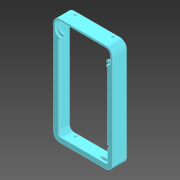
# Autodesk Inventor part: outer shell
Saved by Autodesk Inventor 2020.1 (Build 241239000, 239)
## iProperties
Created: 2026-10-11
Part Number: outer shell
Material: Generic
Document SubType Name: Modeling
Designer: willn
Density: 1 g/cm^3
Appearance: Default
Author: willn
Autodesk Inventor part; units mm, degrees
ref_plane "YZ Plane" through (0, 0, 0) normal (1, 0, 0) x (0, 1, 0)
ref_plane "XZ Plane" through (0, 0, 0) normal (0, 1, 0) x (-1, 0, 0)
ref_plane "XY Plane" through (0, 0, 0) normal (0, 0, 1) x (1, 0, 0)
sketch "Sketch2" plane through (0, 0, 0) normal (0, 0, 1) x (1, 0, 0)
  arc A0 (60, 95.25) -> (56, 99.25) centre (56, 95.25) ccw construction
  line L0 (4, 99.25) -> (56, 99.25) construction
  arc A1 (4, 99.25) -> (0, 95.25) centre (4, 95.25) ccw construction
  line L1 (0, 4) -> (0, 95.25) construction
  arc A2 (0, 4) -> (4, 0) centre (4, 4) ccw construction
  line L2 (56, 0) -> (4, 0) construction
  arc A3 (56, 0) -> (60, 4) centre (56, 4) ccw construction
  line L3 (60, 95.25) -> (60, 4) construction
  circle A4 centre (6.25, 4.05) radius 0.5 construction
  circle A5 centre (14.25, 4.05) radius 0.5 construction
  circle A6 centre (22.2572, 12.9646) radius 0.55 construction
  circle A7 centre (30.0354, 20.7428) radius 0.55 construction
  circle A8 centre (5.5, 27.45) radius 0.5 construction
  circle A9 centre (42.5, 8.25) radius 0.4 construction
  circle A10 centre (42.5, 10.25) radius 0.4 construction
  circle A11 centre (47.88, 23.87) radius 0.375 construction
  circle A12 centre (47.88, 25.87) radius 0.375 construction
  circle A13 centre (54.5, 27.45) radius 0.5 construction
  circle A14 centre (58.15, 29.93) radius 0.5 construction
  circle A15 centre (58.15, 32.47) radius 0.5 construction
  circle A16 centre (58.15, 35.01) radius 0.5 construction
  circle A17 centre (58.15, 37.55) radius 0.5 construction
  circle A18 centre (10.25, 88.95) radius 0.4 construction
  circle A19 centre (5.5, 95.75) radius 0.5 construction
  circle A20 centre (10.25, 90.95) radius 0.4 construction
  arc A21 (19.25, 75.25) -> (18.25, 74.25) centre (19.25, 74.25) ccw construction
  line L4 (40.75, 75.25) -> (19.25, 75.25) construction
  arc A22 (41.75, 74.25) -> (40.75, 75.25) centre (40.75, 74.25) ccw construction
  arc A23 (40.75, 73.25) -> (41.75, 74.25) centre (40.75, 74.25) ccw construction
  line L5 (19.25, 73.25) -> (40.75, 73.25) construction
  arc A24 (18.25, 74.25) -> (19.25, 73.25) centre (19.25, 74.25) ccw construction
  arc A25 (55.85, 77.95) -> (54.85, 76.95) centre (55.85, 76.95) ccw construction
  line L6 (56.85, 77.95) -> (55.85, 77.95) construction
  arc A26 (57.85, 76.95) -> (56.85, 77.95) centre (56.85, 76.95) ccw construction
  line L7 (57.85, 74.95) -> (57.85, 76.95) construction
  arc A27 (56.85, 73.95) -> (57.85, 74.95) centre (56.85, 74.95) ccw construction
  line L8 (55.85, 73.95) -> (56.85, 73.95) construction
  arc A28 (54.85, 74.95) -> (55.85, 73.95) centre (55.85, 74.95) ccw construction
  line L9 (54.85, 76.95) -> (54.85, 74.95) construction
  circle A29 centre (57.15, 84.82) radius 0.5 construction
  circle A30 centre (57.15, 87.36) radius 0.5 construction
  circle A31 centre (57.15, 89.9) radius 0.5 construction
  circle A32 centre (54.5, 95.75) radius 0.5 construction
  circle A33 centre (57.15, 92.44) radius 0.5 construction
  circle A34 centre (57.15, 94.98) radius 0.5 construction
  line L10 (54.05, 116.3) -> (6.05, 116.3) construction
  line L11 (6.05, 116.3) -> (6.05, 96.3) construction
  line L12 (6.05, 96.3) -> (54.05, 96.3) construction
  line L13 (54.05, 96.3) -> (54.05, 116.3) construction
  arc A35 (4, 102.75) -> (-3.5, 95.25) centre (4, 95.25) ccw construction
  line L14 (4, 102.75) -> (56, 102.75) construction
  arc A36 (63.5, 95.25) -> (56, 102.75) centre (56, 95.25) ccw construction
  line L15 (63.5, 95.25) -> (63.5, 4)
  arc A37 (56, -3.5) -> (63.5, 4) centre (56, 4) ccw
  line L16 (56, -3.5) -> (4, -3.5)
  arc A38 (-3.5, 4) -> (4, -3.5) centre (4, 4) ccw
  line L17 (-3.5, 4) -> (-3.5, 95.25)
  arc A39 (4, 97.25) -> (2, 95.25) centre (4, 95.25) ccw
  line L18 (4, 97.25) -> (56, 97.25)
  arc A40 (58, 95.25) -> (56, 97.25) centre (56, 95.25) ccw
  line L19 (58, 95.25) -> (58, 4)
  arc A41 (56, 2) -> (58, 4) centre (56, 4) ccw
  line L20 (56, 2) -> (4, 2)
  arc A42 (2, 4) -> (4, 2) centre (4, 4) ccw
  line L21 (2, 4) -> (2, 95.25)
  line L22 (59.125, 20.605) -> (59.125, 19.22) construction
  line L23 (59.125, 20.605) -> (59.125, 19.22) construction
  line L24 (58.525, 20.605) -> (58.525, 19.22)
  line L25 (59.725, 19.22) -> (59.725, 20.605)
  arc A43 (59.725, 20.605) -> (58.525, 20.605) centre (59.125, 20.605) ccw
  arc A44 (58.525, 19.22) -> (59.725, 19.22) centre (59.125, 19.22) ccw
  line L26 (59.125, 21.205) -> (58, 21.205)
  line L27 (59.125, 18.62) -> (58, 18.62)
  line L28 (-3.5, 95.25) -> (-3.5, 110.8)
  line L29 (63.5, 95.25) -> (63.5, 110.8)
  line L30 (4, 118.3) -> (56, 118.3)
  arc A45 (4, 118.3) -> (-3.5, 110.8) centre (4, 110.8) ccw
  arc A46 (63.5, 110.8) -> (56, 118.3) centre (56, 110.8) ccw
  line L31 (0, 95.25) -> (0, 4) construction
  arc A47 (0, 4) -> (4, 0) centre (4, 4) ccw construction
  line L32 (4, 0) -> (56, 0) construction
  arc A48 (56, 0) -> (60, 4) centre (56, 4) ccw construction
  line L33 (60, 4) -> (60, 95.25) construction
  arc A49 (61.5, 110.8) -> (56, 116.3) centre (56, 110.8) ccw
  line L34 (56, 116.3) -> (4, 116.3)
  arc A50 (4, 116.3) -> (-1.5, 110.8) centre (4, 110.8) ccw
  line L35 (4, 99.35) -> (56, 99.35)
  arc A51 (56, 99.35) -> (61.5, 104.85) centre (56, 104.85) ccw
  arc A52 (-1.5, 104.85) -> (4, 99.35) centre (4, 104.85) ccw
  line L36 (-1.5, 104.85) -> (-1.5, 110.8)
  line L37 (61.5, 104.85) -> (61.5, 110.8)
  point P0 (0, 0)
  point P1 (59.125, 19.9125)
  point P2 (30, 108.525)
  dimension "d2" = 3.5
  dimension "d4" = 2
  dimension "d5" = 1.2
  dimension "d17" = 19.05
  dimension "d18" = 2.1
  dimension "d20" = 2
  constraints: 48 end point, 38 point on circle, 19 tangent, 18 centre point, 4 equal radius, 3 vertical, 2 horizontal, 2 parallel, 2 point on line, 1 collinear, 1 midpoint, 1 perpendicular, 18 other
  measures "d2" distance between parallel lines of L1 L17
  measures "d4" distance between parallel lines of L1 L21
  measures "d5" diameter of A44
  measures "d17" distance between parallel lines of L18 L34
  measures "d18" distance between parallel lines of L18 L35
  measures "d20" distance between parallel lines of L34 L30
extrude "Extrusion2" add sketch "Sketch2" along normal blind 2.4
sketch "Sketch3" plane through (0, 0, 0) normal (0, 0, -1) x (-1, 0, 0)
  arc A0 (-56.0025, 99.3422) -> (-60.2242, 95.2501) centre (-56.107, 95.2263) ccw construction
  line L0 (-60.2242, 95.2501) -> (-60.2242, 3.9999) construction
  arc A1 (-60.2242, 3.9999) -> (-56.0005, -0.0857) centre (-56.1087, 4.0284) ccw construction
  line L1 (-56.0005, -0.0857) -> (-3.999, -0.0739) construction
  arc A2 (-3.999, -0.0739) -> (0.0745, 4.0007) centre (-4.0001, 4.0008) ccw construction
  line L2 (0.0745, 4.0007) -> (0.0776, 95.1644) construction
  arc A3 (0.0776, 95.1644) -> (-3.9967, 99.2887) centre (-4.0016, 95.2093) ccw construction
  line L3 (-3.9967, 99.2887) -> (-56.0025, 99.3422) construction
  circle A4 centre (-6.25, 4.05) radius 0.5 construction
  circle A5 centre (-14.25, 4.05) radius 0.5 construction
  circle A6 centre (-22.2572, 12.9646) radius 0.55 construction
  circle A7 centre (-30.0354, 20.7428) radius 0.55 construction
  circle A8 centre (-5.5, 27.45) radius 0.5 construction
  circle A9 centre (-42.5, 8.25) radius 0.4 construction
  circle A10 centre (-42.5, 10.25) radius 0.4 construction
  circle A11 centre (-47.88, 23.87) radius 0.375 construction
  circle A12 centre (-47.88, 25.87) radius 0.375 construction
  circle A13 centre (-54.5, 27.45) radius 0.5 construction
  circle A14 centre (-58.15, 29.93) radius 0.5 construction
  circle A15 centre (-58.15, 32.47) radius 0.5 construction
  circle A16 centre (-58.15, 35.01) radius 0.5 construction
  circle A17 centre (-58.15, 37.55) radius 0.5 construction
  circle A18 centre (-10.25, 88.95) radius 0.4 construction
  circle A19 centre (-5.5, 95.75) radius 0.5 construction
  circle A20 centre (-10.25, 90.95) radius 0.4 construction
  arc A21 (-18.25, 74.25) -> (-19.25, 75.25) centre (-19.25, 74.25) ccw construction
  arc A22 (-19.25, 73.25) -> (-18.25, 74.25) centre (-19.25, 74.25) ccw construction
  line L4 (-19.25, 73.25) -> (-40.75, 73.25) construction
  arc A23 (-41.75, 74.25) -> (-40.75, 73.25) centre (-40.75, 74.25) ccw construction
  arc A24 (-40.75, 75.25) -> (-41.75, 74.25) centre (-40.75, 74.25) ccw construction
  line L5 (-40.75, 75.25) -> (-19.25, 75.25) construction
  arc A25 (-54.85, 76.95) -> (-55.85, 77.95) centre (-55.85, 76.95) ccw construction
  line L6 (-54.85, 76.95) -> (-54.85, 74.95) construction
  arc A26 (-55.85, 73.95) -> (-54.85, 74.95) centre (-55.85, 74.95) ccw construction
  line L7 (-55.85, 73.95) -> (-56.85, 73.95) construction
  arc A27 (-57.85, 74.95) -> (-56.85, 73.95) centre (-56.85, 74.95) ccw construction
  line L8 (-57.85, 74.95) -> (-57.85, 76.95) construction
  arc A28 (-56.85, 77.95) -> (-57.85, 76.95) centre (-56.85, 76.95) ccw construction
  line L9 (-56.85, 77.95) -> (-55.85, 77.95) construction
  circle A29 centre (-57.15, 84.82) radius 0.5 construction
  circle A30 centre (-57.15, 87.36) radius 0.5 construction
  circle A31 centre (-57.15, 89.9) radius 0.5 construction
  circle A32 centre (-54.5, 95.75) radius 0.5 construction
  circle A33 centre (-57.15, 92.44) radius 0.5 construction
  circle A34 centre (-57.15, 94.98) radius 0.5 construction
  line L10 (-56, 118.3) -> (-4, 118.3) projected
  arc A35 (-56, 118.3) -> (-63.5, 110.8) centre (-56, 110.8) ccw projected
  line L11 (-63.5, 4) -> (-63.5, 110.8) projected
  arc A36 (-63.5, 4) -> (-56, -3.5) centre (-56, 4) ccw projected
  line L12 (-4, -3.5) -> (-56, -3.5) projected
  arc A37 (-4, -3.5) -> (3.5, 4) centre (-4, 4) ccw projected
  line L13 (3.5, 110.8) -> (3.5, 4) projected
  arc A38 (3.5, 110.8) -> (-4, 118.3) centre (-4, 110.8) ccw projected
  line L14 (-60.2742, 3.9997) -> (-60.2742, 95.2503)
  arc A39 (-56.0019, 99.3922) -> (-60.2742, 95.2503) centre (-56.107, 95.2263) ccw
  line L15 (-56.0019, 99.3922) -> (-3.9981, 99.3387)
  arc A40 (0.1276, 95.2542) -> (-3.9981, 99.3387) centre (-4.0016, 95.2093) ccw
  line L16 (0.1276, 95.2542) -> (0.1245, 4.0005)
  arc A41 (-3.9995, -0.1239) -> (0.1245, 4.0005) centre (-4.0001, 4.0008) ccw
  line L17 (-3.9995, -0.1239) -> (-55.9999, -0.1357)
  arc A42 (-60.2742, 3.9997) -> (-55.9999, -0.1357) centre (-56.1087, 4.0284) ccw
  line L18 (-30, 99.3655) -> (-30, 118.3) construction
  line L19 (-56, 118.3) -> (-4, 118.3) construction
  line L20 (-30, 108.8327) -> (-63.5, 108.8327) construction
  line L21 (-63.5, 4) -> (-63.5, 110.8) construction
  arc A43 (-56, 115.0742) -> (-60.2742, 110.8) centre (-56, 110.8) ccw
  line L22 (-56, 115.0742) -> (-4, 115.0742)
  arc A44 (0.2742, 110.8) -> (-4, 115.0742) centre (-4, 110.8) ccw
  line L23 (0.2742, 110.8) -> (0.2742, 4) construction
  arc A45 (-4, -0.2742) -> (0.2742, 4) centre (-4, 4) ccw construction
  line L24 (-4, -0.2742) -> (-56, -0.2742) construction
  arc A46 (-60.2742, 4) -> (-56, -0.2742) centre (-56, 4) ccw construction
  line L25 (-60.2742, 4) -> (-60.2742, 110.8) construction
  arc A47 (-60.2742, 106.8655) -> (-56, 102.5913) centre (-56, 106.8655) ccw
  line L26 (-56, 102.5913) -> (-4, 102.5913)
  arc A48 (-4, 102.5913) -> (0.2742, 106.8655) centre (-4, 106.8655) ccw
  line L27 (-60.2742, 106.8655) -> (-60.2742, 110.8)
  line L28 (0.2742, 106.8655) -> (0.2742, 110.8)
  line L29 (-54.076, 117.6146) -> (-6.076, 117.7018) construction
  line L30 (-54.0396, 97.6146) -> (-54.076, 117.6146) construction
  line L31 (-6.0397, 97.7018) -> (-54.0396, 97.6146) construction
  line L32 (-6.076, 117.7018) -> (-6.0397, 97.7018) construction
  line L33 (-5.8393, 97.4596) -> (-54.2384, 97.4935) construction
  line L34 (-54.2384, 97.4935) -> (-54.2403, 99.3904) construction
  line L35 (-54.2586, 117.863) -> (-5.8763, 117.855) construction
  line L36 (-5.8763, 117.855) -> (-5.8486, 102.5913) construction
  line L37 (-5.8427, 99.3406) -> (-5.8393, 97.4596) construction
  line L38 (-5.8486, 102.5913) -> (-5.8427, 99.3406)
  line L39 (-54.2403, 99.3904) -> (-54.2434, 102.5913)
  line L40 (-54.2434, 102.5913) -> (-54.2586, 117.863) construction
  line L41 (-54.05, 116.3) -> (-6.05, 116.3) construction
  line L42 (-54.05, 96.3) -> (-54.05, 116.3) construction
  line L43 (-6.05, 96.3) -> (-54.05, 96.3) construction
  line L44 (-6.05, 116.3) -> (-6.05, 96.3) construction
  line L45 (-4, 116.3) -> (-56, 116.3) construction
  line L46 (-54.257, 116.3) -> (-54.2558, 115.0742)
  line L47 (-54.257, 116.3) -> (-5.8735, 116.3)
  line L48 (-5.8735, 116.3) -> (-5.8713, 115.0742)
  point P0 (0, 0)
  dimension "d8" = 0.05
  dimension "d13" = 0.2
  constraints: 76 end point, 45 centre point, 44 point on circle, 13 point on line, 6 collinear, 6 symmetric about line, 3 midpoint, 1 parallel, 1 perpendicular, 1 tangent, 16 other
  measures "d8" distance between parallel lines of L0 L14
  measures "d13" distance between parallel lines of L32 L36
extrude "Extrusion3" add sketch "Sketch3" along normal blind 1.5
sketch "Sketch4" plane through (0, 0, -1.5) normal (0, 0, -1) x (-1, 0, 0)
  arc A0 (-56, 118.3) -> (-63.5, 110.8) centre (-56, 110.8) ccw projected
  line L0 (-63.5, 110.8) -> (-63.5, 4) projected
  arc A1 (-63.5, 4) -> (-56, -3.5) centre (-56, 4) ccw projected
  line L1 (-56, -3.5) -> (-4, -3.5) projected
  arc A2 (-4, -3.5) -> (3.5, 4) centre (-4, 4) ccw projected
  line L2 (3.5, 4) -> (3.5, 110.8) projected
  arc A3 (3.5, 110.8) -> (-4, 118.3) centre (-4, 110.8) ccw projected
  line L3 (-4, 118.3) -> (-56, 118.3) projected
  arc A4 (-60.2742, 3.9997) -> (-55.9999, -0.1357) centre (-56.1087, 4.0284) ccw construction
  line L4 (-61.4, 4) -> (-61.4, 110.8)
  arc A5 (-56, 116.2) -> (-61.4, 110.8) centre (-56, 110.8) ccw
  line L5 (-56, 116.2) -> (-4, 116.2)
  arc A6 (1.4, 110.8) -> (-4, 116.2) centre (-4, 110.8) ccw
  line L6 (1.4, 110.8) -> (1.4, 4)
  arc A7 (-4, -1.4) -> (1.4, 4) centre (-4, 4) ccw
  line L7 (-4, -1.4) -> (-56, -1.4)
  arc A8 (-61.4, 4) -> (-56, -1.4) centre (-56, 4) ccw
  point P0 (0, 0)
  dimension "d16" = 2.1
  constraints: 8 end point, 8 point on circle, 4 centre point, 7 other
  measures "d16" distance between parallel lines of L0 L4
extrude "Extrusion4" add sketch "Sketch4" along normal blind 12.11
sketch "Sketch5" plane through (4, -3.5, 2.4) normal (0, -1, 0) x (1, 0, 0)
  line L0 (47.3513, -6.495) -> (47.3513, -7.205) construction
  arc A0 (46.1013, -8.455) -> (47.3513, -7.205) centre (46.1013, -7.205) ccw construction
  line L1 (46.1013, -8.455) -> (39.6613, -8.455) construction
  arc A1 (38.4113, -7.205) -> (39.6613, -8.455) centre (39.6613, -7.205) ccw construction
  line L2 (38.4113, -7.205) -> (38.4113, -6.495) construction
  arc A2 (39.6613, -5.245) -> (38.4113, -6.495) centre (39.6613, -6.495) ccw construction
  line L3 (39.6613, -5.245) -> (46.1013, -5.245) construction
  arc A3 (47.3513, -6.495) -> (46.1013, -5.245) centre (46.1013, -6.495) ccw construction
  line L4 (46.1013, -5.045) -> (39.6613, -5.045)
  arc A4 (39.6613, -5.045) -> (38.2113, -6.495) centre (39.6613, -6.495) ccw
  line L5 (38.2113, -6.495) -> (38.2113, -7.205)
  arc A5 (38.2113, -7.205) -> (39.6613, -8.655) centre (39.6613, -7.205) ccw
  line L6 (39.6613, -8.655) -> (46.1013, -8.655)
  arc A6 (46.1013, -8.655) -> (47.5513, -7.205) centre (46.1013, -7.205) ccw
  line L7 (47.5513, -7.205) -> (47.5513, -6.495)
  arc A7 (47.5513, -6.495) -> (46.1013, -5.045) centre (46.1013, -6.495) ccw
  point P0 (-4, -2.4)
  dimension "d21" = 0.2
  constraints: 16 end point, 16 point on circle, 8 centre point, 2 horizontal, 2 vertical, 23 other
  measures "d21" distance between parallel lines of L3 L4
extrude "Extrusion5" cut sketch "Sketch5" against normal blind 10
sketch "Sketch6" plane through (4, -3.5, 2.4) normal (0, -1, 0) x (1, 0, 0)
  line L0 (8.3339, -0.715) -> (7.3256, -0.715) construction
  line L1 (0.07, -0.565) -> (7.3256, -0.565) construction
  line L2 (7.3256, -0.565) -> (8.3339, -0.565) construction
  line L3 (8.3339, -0.565) -> (10.7361, -0.565) construction
  line L4 (11.8441, -0.565) -> (10.7361, -0.565) construction
  arc A0 (0.07, -0.565) -> (-0.23, -0.865) centre (0.07, -0.865) ccw construction
  line L5 (-0.23, -0.865) -> (-0.23, -2.365) construction
  line L6 (11.8441, -0.565) -> (14.22, -0.565) construction
  arc A1 (14.52, -0.865) -> (14.22, -0.565) centre (14.22, -0.865) ccw construction
  line L7 (14.52, -2.365) -> (14.52, -0.865) construction
  line L8 (-0.23, -2.365) -> (-0.03, -2.365) construction
  line L9 (14.32, -2.365) -> (14.52, -2.365) construction
  line L10 (14.32, -2.565) -> (14.72, -2.565)
  line L11 (14.72, -2.565) -> (14.72, -0.865)
  arc A2 (14.72, -0.865) -> (14.22, -0.365) centre (14.22, -0.865) ccw
  line L12 (14.22, -0.365) -> (11.8441, -0.365)
  line L13 (11.8441, -0.365) -> (10.7361, -0.365)
  line L14 (10.7361, -0.365) -> (8.3339, -0.365)
  line L15 (8.3339, -0.365) -> (7.3256, -0.365)
  line L16 (7.3256, -0.365) -> (0.07, -0.365)
  arc A3 (0.07, -0.365) -> (-0.43, -0.865) centre (0.07, -0.865) ccw
  line L17 (-0.43, -0.865) -> (-0.43, -2.565)
  line L18 (-0.43, -2.565) -> (-0.03, -2.565)
  line L19 (-0.03, -2.565) -> (14.32, -2.565)
  point P0 (-4, -2.4)
  dimension "d25" = 0.2
  constraints: 40 end point, 8 horizontal, 8 point on circle, 4 centre point, 2 vertical, 29 other
  measures "d25" distance between parallel lines of L1 L16
extrude "Extrusion6" cut sketch "Sketch6" against normal blind 10
sketch "Sketch7" plane through (4, -3.5, 2.4) normal (0, -1, 0) x (1, 0, 0)
  line L0 (52, -16.01) -> (0, -16.01) projected
  line L1 (4.5, -12.51) -> (47.5, -12.51) construction
  line L2 (52, -16.01) -> (0, -16.01) projected
  line L3 (26, -16.01) -> (26, -12.51) construction
  point P0 (-4, -2.4)
  dimension "d28" = 3.5
  dimension "d29" = 43
  constraints: 4 end point, 3 midpoint, 1 horizontal, 1 horizontal alignment, 1 vertical
  measures "d28" distance from line of L0 L1.start
  measures "d29" distance of L1.start L1.end
hole "Hole1" at (8.5, -3.5, -10.11) at (51.5, -3.5, -10.11) direction (0, 1, 0) diameter 2.9 end through all clearance for "Socket Head Cap Screw ISO 4762" size "M2.5" standard "ISO"
fillet "Fillet1" radius 0.6 2 edges at (58, 21.205, 1.2) (58, 18.62, 1.2)
sketch "Sketch8" plane through (0, 0, 2.4) normal (0, 0, 1) x (1, 0, 0)
  arc A0 (58, 95.25) -> (56, 99.35) centre (52.7975, 95.25) ccw
  arc A1 (55.2742, 95.7761) -> (54.8242, 96.2261) centre (54.8242, 95.7761) ccw construction
  arc A2 (55.3414, 95.25) -> (54.3634, 97.2548) centre (52.7975, 95.25) ccw
  line L0 (58, 95.25) -> (58, 21.805) projected
  line L1 (56, 99.35) -> (4, 99.35) projected
  line L2 (4, 97.25) -> (56, 97.25) projected
  arc A3 (58, 95.25) -> (56, 97.25) centre (56, 95.25) ccw projected
  line L3 (56, 99.35) -> (52.3054, 102.2359)
  line L4 (54.3634, 97.2548) -> (51.681, 99.35)
  line L5 (56, 118.3) -> (4, 118.3) construction
  line L6 (30, 118.3) -> (30, 97.25) construction
  line L7 (4, 97.25) -> (56, 97.25) construction
  arc A4 (4, 99.35) -> (2, 95.25) centre (7.2025, 95.25) ccw
  arc A5 (5.6366, 97.2548) -> (4.6586, 95.25) centre (7.2025, 95.25) ccw
  line L8 (5.6366, 97.2548) -> (8.319, 99.35)
  arc A6 (4, 97.25) -> (2, 95.25) centre (4, 95.25) ccw
  point P0 (0, 0)
  point P1 (54.2476, 97.25)
  point P2 (54.3695, 97.25)
  constraints: 12 point on circle, 8 end point, 6 centre point, 6 symmetric about line, 4 tangent, 2 midpoint, 1 parallel, 1 point on line, 7 other
extrude "Extrusion7" cut sketch "Sketch8" against normal up to surface (2.4 mm away)
fillet "Fillet2" radius 0.3 2 edges at (4, 99.35, 1.2) (56, 99.35, 1.2)
fillet "Fillet2" radius 1.5 4 edges at (54.2434, 102.5913, -0.75) (54.2403, 99.3904, -0.75) (5.8486, 102.5913, -0.75) (5.8427, 99.3406, -0.75)
body "Solid2"
